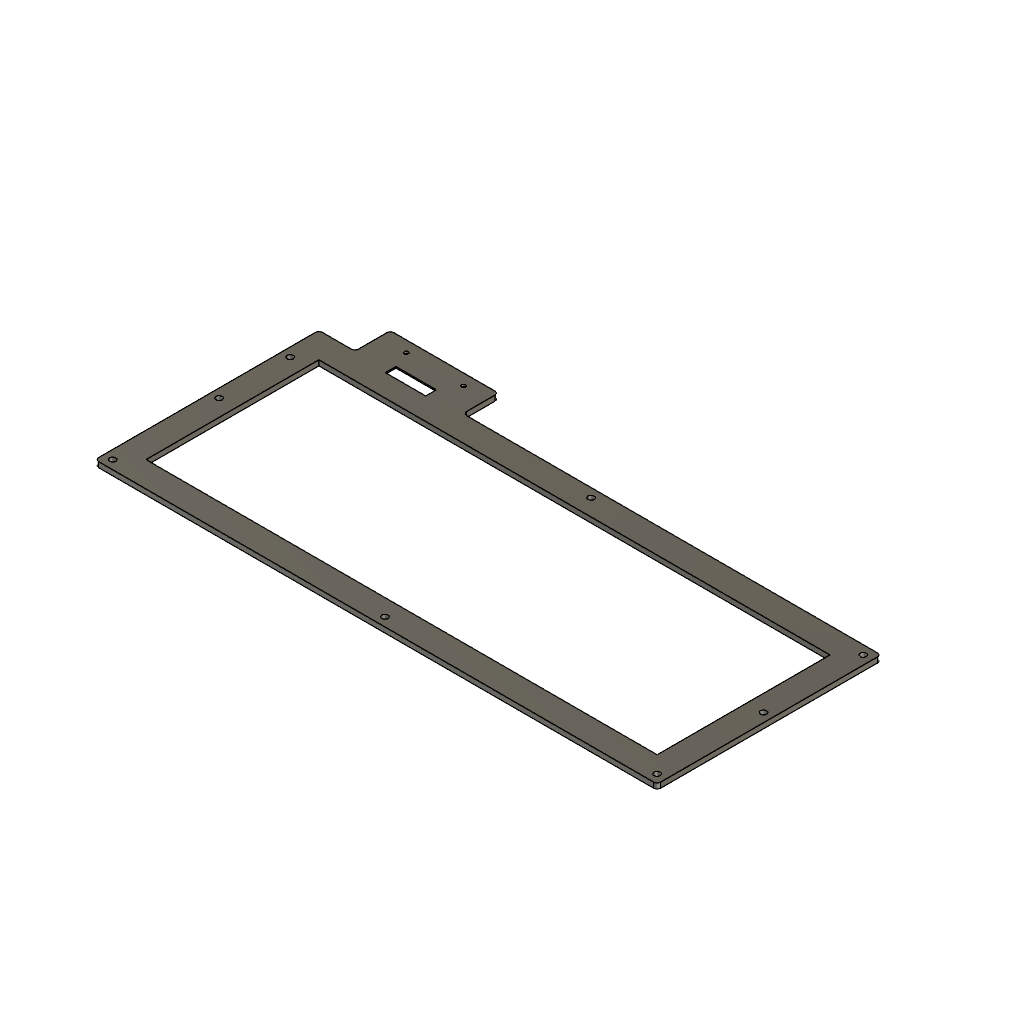
PW67_Upper_Frame_OLED (Autodesk Fusion 360 design; units mm, degrees)
part number: 2026-10-11-22-41-56-035
Autodesk Fusion 360 part; units mm, degrees
sketch "Clamping frame with provisional keycap travel opening" plane through (0, 0, 0) normal (0, 0, 1) x (1, 0, 0)
  line L0 (34.35, -164.925) -> (350.85, -164.925)
  line L1 (350.85, -164.925) -> (350.85, -38.85)
  line L2 (350.85, -38.85) -> (115.525, -38.85)
  line L3 (115.525, -38.85) -> (115.525, -18.875)
  line L4 (115.525, -18.875) -> (54.6, -18.875)
  line L5 (54.6, -18.875) -> (54.6, -38.85)
  line L6 (54.6, -38.85) -> (34.35, -38.85)
  line L7 (34.35, -38.85) -> (34.35, -164.925)
  line L8 (48.7325, -150.525) -> (336.4825, -150.525)
  line L9 (336.4825, -150.525) -> (336.4825, -53.275)
  line L10 (336.4825, -53.275) -> (48.7325, -53.275)
  line L11 (48.7325, -53.275) -> (48.7325, -150.525)
  line L12 (64.6, -49.65) -> (105.525, -49.65)
  line L13 (105.525, -49.65) -> (105.525, -28.875)
  line L14 (105.525, -28.875) -> (64.6, -28.875)
  line L15 (64.6, -28.875) -> (64.6, -49.65)
extrude "Upper frame bearing directly on plate" add sketch "Clamping frame with provisional keycap travel opening" along normal blind 3 from surface at 6.51 makes body 1
sketch "Eight M3 through-bolts - outside PCB" plane through (0, 0, 0) normal (0, 0, 1) x (1, 0, 0)
  circle A0 centre (39.35, -159.925) radius 1.7
  circle A1 centre (192.6, -159.925) radius 1.7
  circle A2 centre (345.85, -159.925) radius 1.7
  circle A3 centre (39.35, -100) radius 1.7
  circle A4 centre (345.85, -100) radius 1.7
  circle A5 centre (39.35, -60) radius 1.7
  circle A6 centre (192.6, -43.85) radius 1.7
  circle A7 centre (345.85, -43.85) radius 1.7
extrude "Aligned 3.4mm through-holes" cut sketch "Eight M3 through-bolts - outside PCB" along normal blind 3 from surface at 6.51 bodies 1
fillet "Rounded exterior corners - prototype" radius 2 8 edges at (34.35, -38.85, 8.01) (54.6, -38.85, 8.01) (54.6, -18.875, 8.01) (115.525, -18.875, 8.01) (115.525, -38.85, 8.01) (350.85, -38.85, 8.01) (350.85, -164.925, 8.01) (34.35, -164.925, 8.01) on bodies 1
ref_plane "WorkPlane1" through (0, 0, 6.51) normal (0, 0, 1) x (1, 0, 0)
sketch "OLED integral bezel" plane through (0, 0, 6.51) normal (0, 0, 1) x (1, 0, 0)
  line L0 (64.55, -49.7) -> (105.575, -49.7)
  line L1 (105.575, -49.7) -> (105.575, -28.825)
  line L2 (105.575, -28.825) -> (64.55, -28.825)
  line L3 (64.55, -28.825) -> (64.55, -49.7)
  dimension "d84" = 41.025
  dimension "d85" = 20.875
  dimension "d86" = 64.55
  dimension "d87" = 49.7
  measures "d84" horizontal distance of L0.start L1.end
  measures "d85" vertical distance of L0.start L1.end
  measures "d86" horizontal distance of origin L0.start
  measures "d87" vertical distance of origin L0.start
extrude "OLED integral bezel (1)" add sketch "OLED integral bezel" along normal blind 3 bodies 1
ref_plane "WorkPlane2" through (0, 0, 6.51) normal (0, 0, 1) x (1, 0, 0)
sketch "OLED underside PCB pocket" plane through (0, 0, 6.51) normal (0, 0, 1) x (1, 0, 0)
  line L0 (65.85, -44.3) -> (104.85, -44.3)
  line L1 (104.85, -44.3) -> (104.85, -31.3)
  line L2 (104.85, -31.3) -> (65.85, -31.3)
  line L3 (65.85, -31.3) -> (65.85, -44.3)
  dimension "d92" = 39
  dimension "d93" = 13
  dimension "d94" = 65.85
  dimension "d95" = 44.3
  measures "d92" horizontal distance of L0.start L1.end
  measures "d93" vertical distance of L0.start L1.end
  measures "d94" horizontal distance of origin L0.start
  measures "d95" vertical distance of origin L0.start
extrude "OLED underside PCB pocket (1)" cut sketch "OLED underside PCB pocket" along normal blind 0.6 bodies 1
ref_plane "WorkPlane3" through (0, 0, 7.11) normal (0, 0, 1) x (1, 0, 0)
sketch "OLED glass and flex relief" plane through (0, 0, 7.11) normal (0, 0, 1) x (1, 0, 0)
  line L0 (70.75, -43.9) -> (104.55, -43.9)
  line L1 (104.55, -43.9) -> (104.55, -31.7)
  line L2 (104.55, -31.7) -> (70.75, -31.7)
  line L3 (70.75, -31.7) -> (70.75, -43.9)
  dimension "d100" = 33.8
  dimension "d101" = 12.2
  dimension "d102" = 70.75
  dimension "d103" = 43.9
  measures "d100" horizontal distance of L0.start L1.end
  measures "d101" vertical distance of L0.start L1.end
  measures "d102" horizontal distance of origin L0.start
  measures "d103" vertical distance of origin L0.start
extrude "OLED glass and flex relief (1)" cut sketch "OLED glass and flex relief" along normal blind 1.6 bodies 1
ref_plane "WorkPlane4" through (0, 0, 7.11) normal (0, 0, 1) x (1, 0, 0)
sketch "OLED active-area viewing window" plane through (0, 0, 7.11) normal (0, 0, 1) x (1, 0, 0)
  line L0 (73.71, -40.74) -> (96.39, -40.74)
  line L1 (96.39, -40.74) -> (96.39, -34.86)
  line L2 (96.39, -34.86) -> (73.71, -34.86)
  line L3 (73.71, -34.86) -> (73.71, -40.74)
  dimension "d108" = 22.68
  dimension "d109" = 5.88
  dimension "d110" = 73.71
  dimension "d111" = 40.74
  measures "d108" horizontal distance of L0.start L1.end
  measures "d109" vertical distance of L0.start L1.end
  measures "d110" horizontal distance of origin L0.start
  measures "d111" vertical distance of origin L0.start
extrude "OLED active-area viewing window (1)" cut sketch "OLED active-area viewing window" along normal blind 2.5 bodies 1
ref_plane "WorkPlane5" through (0, 0, 6.51) normal (0, 0, 1) x (1, 0, 0)
sketch "OLED four-wire service passage" plane through (0, 0, 6.51) normal (0, 0, 1) x (1, 0, 0)
  line L0 (64.6, -39.8) -> (70.3, -39.8)
  line L1 (70.3, -39.8) -> (70.3, -35.8)
  line L2 (70.3, -35.8) -> (64.6, -35.8)
  line L3 (64.6, -35.8) -> (64.6, -39.8)
  dimension "d116" = 5.7
  dimension "d117" = 4
  dimension "d118" = 64.6
  dimension "d119" = 39.8
  measures "d116" horizontal distance of L0.start L1.end
  measures "d117" vertical distance of L0.start L1.end
  measures "d118" horizontal distance of origin L0.start
  measures "d119" vertical distance of origin L0.start
extrude "OLED four-wire service passage (1)" cut sketch "OLED four-wire service passage" along normal blind 1.8 bodies 1
ref_plane "WorkPlane6" through (0, 0, 6.51) normal (0, 0, 1) x (1, 0, 0)
sketch "OLED A recessed screw-tab seat" plane through (0, 0, 6.51) normal (0, 0, 1) x (1, 0, 0)
  line L0 (66.7, -29.6) -> (73.1, -29.6)
  line L1 (73.1, -29.6) -> (73.1, -22)
  line L2 (73.1, -22) -> (66.7, -22)
  line L3 (66.7, -22) -> (66.7, -29.6)
  dimension "d124" = 6.4
  dimension "d125" = 7.6
  dimension "d126" = 66.7
  dimension "d127" = 29.6
  measures "d124" horizontal distance of L0.start L1.end
  measures "d125" vertical distance of L0.start L1.end
  measures "d126" horizontal distance of origin L0.start
  measures "d127" vertical distance of origin L0.start
extrude "OLED A recessed screw-tab seat (1)" cut sketch "OLED A recessed screw-tab seat" along normal blind 1.9 bodies 1
ref_plane "WorkPlane7" through (0, 0, 6.51) normal (0, 0, 1) x (1, 0, 0)
sketch "OLED A clip neck clearance" plane through (0, 0, 6.51) normal (0, 0, 1) x (1, 0, 0)
  line L0 (66.7, -31.1) -> (73.1, -31.1)
  line L1 (73.1, -31.1) -> (73.1, -28.5)
  line L2 (73.1, -28.5) -> (66.7, -28.5)
  line L3 (66.7, -28.5) -> (66.7, -31.1)
  dimension "d132" = 6.4
  dimension "d133" = 2.6
  dimension "d134" = 66.7
  dimension "d135" = 31.1
  measures "d132" horizontal distance of L0.start L1.end
  measures "d133" vertical distance of L0.start L1.end
  measures "d134" horizontal distance of origin L0.start
  measures "d135" vertical distance of origin L0.start
extrude "OLED A clip neck clearance (1)" cut sketch "OLED A clip neck clearance" along normal blind 1.9 bodies 1
ref_plane "WorkPlane8" through (0, 0, 6.51) normal (0, 0, 1) x (1, 0, 0)
sketch "Integral M2 roof boss A" plane through (0, 0, 6.51) normal (0, 0, 1) x (1, 0, 0)
  circle A0 centre (69.9, -25.2) radius 1.15
  dimension "d184" = 2.3
  dimension "d262" = 69.9
  measures "d184" diameter of A0
  measures "d262" horizontal distance of origin A0.centre
extrude "Integral M2 roof boss A (1)" cut sketch "Integral M2 roof boss A" along normal blind 3.1 bodies 1
ref_plane "WorkPlane9" through (0, 0, 6.51) normal (0, 0, 1) x (1, 0, 0)
sketch "OLED B recessed screw-tab seat" plane through (0, 0, 6.51) normal (0, 0, 1) x (1, 0, 0)
  line L0 (99, -29.6) -> (105.4, -29.6)
  line L1 (105.4, -29.6) -> (105.4, -22)
  line L2 (105.4, -22) -> (99, -22)
  line L3 (99, -22) -> (99, -29.6)
  dimension "d194" = 6.4
  dimension "d195" = 7.6
  dimension "d196" = 99
  dimension "d197" = 29.6
  measures "d194" horizontal distance of L0.start L1.end
  measures "d195" vertical distance of L0.start L1.end
  measures "d196" horizontal distance of origin L0.start
  measures "d197" vertical distance of origin L0.start
extrude "OLED B recessed screw-tab seat (1)" cut sketch "OLED B recessed screw-tab seat" along normal blind 1.9 bodies 1
ref_plane "WorkPlane10" through (0, 0, 6.51) normal (0, 0, 1) x (1, 0, 0)
sketch "OLED B clip neck clearance" plane through (0, 0, 6.51) normal (0, 0, 1) x (1, 0, 0)
  line L0 (99, -31.1) -> (105.4, -31.1)
  line L1 (105.4, -31.1) -> (105.4, -28.5)
  line L2 (105.4, -28.5) -> (99, -28.5)
  line L3 (99, -28.5) -> (99, -31.1)
  dimension "d202" = 6.4
  dimension "d203" = 2.6
  dimension "d204" = 99
  dimension "d205" = 31.1
  measures "d202" horizontal distance of L0.start L1.end
  measures "d203" vertical distance of L0.start L1.end
  measures "d204" horizontal distance of origin L0.start
  measures "d205" vertical distance of origin L0.start
extrude "OLED B clip neck clearance (1)" cut sketch "OLED B clip neck clearance" along normal blind 1.9 bodies 1
ref_plane "WorkPlane11" through (0, 0, 6.51) normal (0, 0, 1) x (1, 0, 0)
sketch "Integral M2 roof boss B" plane through (0, 0, 6.51) normal (0, 0, 1) x (1, 0, 0)
  circle A0 centre (102.2, -25.2) radius 1.15
  dimension "d254" = 2.3
  dimension "d264" = 102.2
  measures "d254" diameter of A0
  measures "d264" horizontal distance of origin A0.centre
extrude "Integral M2 roof boss B (1)" cut sketch "Integral M2 roof boss B" along normal blind 3.1 bodies 1
ref_plane "WorkPlane12" through (0, 0, 7.11) normal (0, 0, 1) x (1, 0, 0)
sketch "OLED solder-pad ring relief" plane through (0, 0, 7.11) normal (0, 0, 1) x (1, 0, 0)
  line L0 (66.4, -43) -> (69.2, -43)
  line L1 (69.2, -43) -> (69.2, -32.5)
  line L2 (69.2, -32.5) -> (66.4, -32.5)
  line L3 (66.4, -32.5) -> (66.4, -43)
  dimension "d278" = 2.8
  dimension "d279" = 10.5
  dimension "d280" = 66.4
  dimension "d281" = 43
  measures "d278" horizontal distance of L0.start L1.end
  measures "d279" vertical distance of L0.start L1.end
  measures "d280" horizontal distance of origin L0.start
  measures "d281" vertical distance of origin L0.start
extrude "OLED solder-pad ring relief (1)" cut sketch "OLED solder-pad ring relief" along normal blind 0.2 bodies 1
ref_plane "WorkPlane13" through (0, 0, 7.11) normal (0, 0, 1) x (1, 0, 0)
sketch "OLED third bare-PCB upper stop - verify physical module" plane through (0, 0, 7.11) normal (0, 0, 1) x (1, 0, 0)
  line L0 (101.1, -32.2) -> (104.4, -32.2)
  line L1 (104.4, -32.2) -> (104.4, -31.8)
  line L2 (104.4, -31.8) -> (101.1, -31.8)
  line L3 (101.1, -31.8) -> (101.1, -32.2)
  dimension "d286" = 3.3
  dimension "d287" = 0.4
  dimension "d288" = 101.1
  dimension "d289" = 32.2
  measures "d286" horizontal distance of L0.start L1.end
  measures "d287" vertical distance of L0.start L1.end
  measures "d288" horizontal distance of origin L0.start
  measures "d289" vertical distance of origin L0.start
extrude "OLED third bare-PCB upper stop - verify physical module (1)" add sketch "OLED third bare-PCB upper stop - verify physical module" along normal blind 2.4 separate body makes body 2
combine "OLED PCB stop integrated into bezel roof" operation add target body 1 tool bodies 2
equation "d28 = plateTop"
equation "d29 = upperFrameThickness"
equation "d37 = plateTop"
equation "d38 = upperFrameThickness"
equation "d82 = ( oledFrameBottomZ ) - 9.855000000000002 mm"
equation "d87 = -( -49.7 mm )"
equation "d88 = oledFrameTopZ - oledFrameBottomZ"
equation "d90 = ( oledFrameBottomZ ) - 9.855000000000002 mm"
equation "d92 = oledPCBLength + 2 * oledMountClearance"
equation "d93 = oledPCBWidth + 2 * oledMountClearance"
equation "d94 = oledCenterX - oledPCBLength / 2 - oledMountClearance"
equation "d95 = -( oledCenterY - oledPCBWidth / 2 - oledMountClearance )"
equation "d96 = oledRecessDepth"
equation "d98 = ( oledPCBTopZ ) - 9.855000000000002 mm"
equation "d102 = oledCenterX - 14.6 mm"
equation "d103 = -( oledCenterY - 6.1 mm )"
equation "d104 = oledGlassHeight + oledGlassClearance"
equation "d106 = ( oledPCBTopZ ) - 9.855000000000002 mm"
equation "d108 = oledActiveLength + 2 * oledWindowMargin"
equation "d109 = oledActiveWidth + 2 * oledWindowMargin"
equation "d110 = oledCenterX - oledNominalLength / 2 + oledActiveOffsetX - oledWindowMargin"
equation "d111 = -( oledCenterY + oledActiveOffsetY - oledActiveWidth / 2 - oledWindowMargin )"
equation "d112 = oledFrameTopZ - oledPCBTopZ + 0.1 mm"
equation "d114 = ( oledFrameBottomZ ) - 9.855000000000002 mm"
equation "d117 = oledCableWidth"
equation "d119 = -( oledCenterY - oledCableWidth / 2 )"
equation "d120 = oledCableDepth"
equation "d122 = ( oledFrameBottomZ ) - 9.855000000000002 mm"
equation "d124 = 6 mm + 2 * oledTabClearance"
equation "d125 = 7.2 mm + 2 * oledTabClearance"
equation "d126 = oledScrewLeftX - 3 mm - oledTabClearance"
equation "d127 = -( oledScrewY - 4.2 mm - oledTabClearance )"
equation "d128 = oledEarBottomZ + oledEarThickness - oledFrameBottomZ"
equation "d130 = ( oledFrameBottomZ ) - 9.855000000000002 mm"
equation "d132 = 6 mm + 2 * oledTabClearance"
equation "d134 = oledScrewLeftX - ( 6 mm ) / 2 - oledTabClearance"
equation "d135 = -( -31.1 mm )"
equation "d136 = oledEarBottomZ + oledEarThickness - oledFrameBottomZ"
equation "d182 = ( oledFrameBottomZ ) - 9.855000000000002 mm"
equation "d184 = oledScrewClearance"
equation "d185 = oledFrameTopZ - oledFrameBottomZ + 0.1 mm"
equation "d192 = ( oledFrameBottomZ ) - 9.855000000000002 mm"
equation "d194 = 6 mm + 2 * oledTabClearance"
equation "d195 = 7.2 mm + 2 * oledTabClearance"
equation "d196 = oledScrewRightX - 3 mm - oledTabClearance"
equation "d197 = -( oledScrewY - 4.2 mm - oledTabClearance )"
equation "d198 = oledEarBottomZ + oledEarThickness - oledFrameBottomZ"
equation "d200 = ( oledFrameBottomZ ) - 9.855000000000002 mm"
equation "d202 = 6 mm + 2 * oledTabClearance"
equation "d204 = oledScrewRightX - ( 6 mm ) / 2 - oledTabClearance"
equation "d205 = -( -31.1 mm )"
equation "d206 = oledEarBottomZ + oledEarThickness - oledFrameBottomZ"
equation "d252 = ( oledFrameBottomZ ) - 9.855000000000002 mm"
equation "d254 = oledScrewClearance"
equation "d255 = oledFrameTopZ - oledFrameBottomZ + 0.1 mm"
equation "d262 = oledScrewLeftX"
equation "d263 = -oledScrewY"
equation "d264 = oledScrewRightX"
equation "d265 = -oledScrewY"
equation "d276 = ( oledPCBTopZ ) - 9.855000000000002 mm"
equation "d281 = -( -43 mm )"
equation "d284 = ( oledPCBTopZ ) - 9.855000000000002 mm"
equation "d289 = -( -32.2 mm )"
equation "d290 = oledFrameTopZ - oledPCBTopZ"
equation "pcbTop = 1.51 mm" comment "Measured imported PCB top"
equation "plateTop = pcbTop + 5 mm" comment "ai03 nominal MX plate top above PCB"
equation "upperFrameThickness = 3 mm" comment "Provisional printed frame thickness"
equation "oledPCBLength = 38.5 mm" comment "PW67 OLED; supplier tolerances and physical module must be verified"
equation "oledPCBWidth = 12.5 mm" comment "PW67 OLED; supplier tolerances and physical module must be verified"
equation "oledActiveLength = 22.38 mm" comment "PW67 OLED; supplier tolerances and physical module must be verified"
equation "oledActiveWidth = 5.58 mm" comment "PW67 OLED; supplier tolerances and physical module must be verified"
equation "oledActiveOffsetX = 7.51 mm" comment "PW67 OLED; supplier tolerances and physical module must be verified"
equation "oledActiveOffsetY = 0 mm" comment "PW67 OLED; supplier tolerances and physical module must be verified"
equation "oledMountClearance = 0.25 mm" comment "PW67 OLED; supplier tolerances and physical module must be verified"
equation "oledNominalLength = 38 mm" comment "PW67 OLED; supplier tolerances and physical module must be verified"
equation "oledCenterX = 85.35 mm" comment "PW67 OLED; supplier tolerances and physical module must be verified"
equation "oledCenterY = -37.8 mm" comment "PW67 OLED; supplier tolerances and physical module must be verified"
equation "oledFrameBottomZ = 16.365 mm" comment "PW67 OLED; supplier tolerances and physical module must be verified"
equation "oledFrameTopZ = 19.365 mm" comment "PW67 OLED; supplier tolerances and physical module must be verified"
equation "oledRecessDepth = 0.6 mm" comment "PW67 OLED; supplier tolerances and physical module must be verified"
equation "oledPCBTopZ = oledFrameBottomZ + oledRecessDepth" comment "PW67 OLED; supplier tolerances and physical module must be verified"
equation "oledGlassHeight = 1.4 mm" comment "PW67 OLED; supplier tolerances and physical module must be verified"
equation "oledGlassClearance = 0.2 mm" comment "PW67 OLED; supplier tolerances and physical module must be verified"
equation "oledScrewLeftX = 69.9 mm" comment "PW67 OLED; supplier tolerances and physical module must be verified"
equation "oledScrewRightX = 102.2 mm" comment "PW67 OLED; supplier tolerances and physical module must be verified"
equation "oledScrewY = -25.2 mm" comment "PW67 OLED; supplier tolerances and physical module must be verified"
equation "oledScrewClearance = 2.3 mm" comment "PW67 OLED; supplier tolerances and physical module must be verified"
equation "oledEarBottomZ = 16.665 mm" comment "PW67 OLED; supplier tolerances and physical module must be verified"
equation "oledEarThickness = 1.6 mm" comment "PW67 OLED; supplier tolerances and physical module must be verified"
equation "oledTabClearance = 0.2 mm" comment "PW67 OLED; supplier tolerances and physical module must be verified"
equation "oledWindowMargin = 0.15 mm" comment "PW67 OLED; supplier tolerances and physical module must be verified"
equation "oledCableWidth = 4 mm" comment "PW67 OLED; supplier tolerances and physical module must be verified"
equation "oledCableDepth = 1.8 mm" comment "PW67 OLED; supplier tolerances and physical module must be verified"
named bodies: "Upper Frame"
